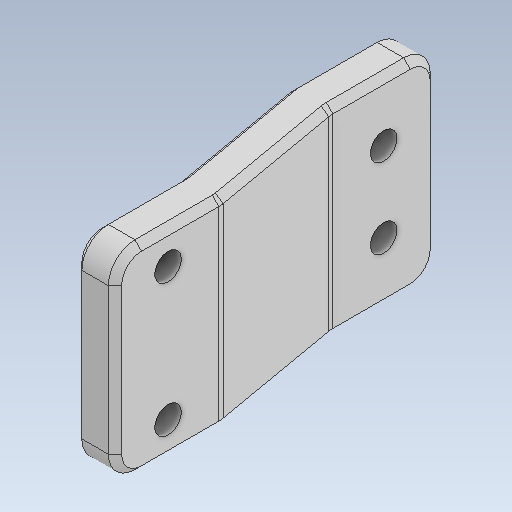
# Autodesk Inventor part: rali-x support_V2
Saved by Autodesk Inventor 2026.2 (Build 302298010, 298A)
## iProperties
Created: 2026-04-29
Part Number: rali-x support_V2
Material: 일반
Document SubType Name: Modeling
Designer: khw
Density: 1 g/cm^3
Appearance: 기본값
Author: khw
Autodesk Inventor part; units mm, degrees
ref_plane "YZ Plane" through (0, 0, 0) normal (1, 0, 0) x (0, 1, 0)
ref_plane "XZ Plane" through (0, 0, 0) normal (0, 1, 0) x (-1, 0, 0)
ref_plane "XY Plane" through (0, 0, 0) normal (0, 0, 1) x (1, 0, 0)
sketch "스케치1" plane through (0, 0, 0) normal (0, 1, 0) x (-1, 0, 0)
  line L0 (0, 0) -> (0, -16)
  line L1 (0, -16) -> (3.5, -36)
  line L2 (3.5, -52) -> (9.5, -52)
  line L3 (9.5, -52) -> (9.5, -36)
  line L4 (9.5, -36) -> (6, -16)
  line L5 (6, -16) -> (6, 0)
  line L6 (6, 0) -> (0, 0)
  line L7 (0, -16) -> (6, -16) construction
  line L8 (3.5, -36) -> (9.5, -36) construction
  line L9 (3.5, -36) -> (3.5, -52)
  point P0 (0, -8)
  point P1 (9.5, -44)
  dimension "d0" = 6
  dimension "d2" = 20
  dimension "d3" = 6
  dimension "d4" = 3.5
  dimension "d5" = 16
  dimension "d6" = 16
  constraints: 20 end point, 4 parallel, 2 midpoint, 2 perpendicular, 1 vertical
  measures "d0" distance from line of L5 point (0, -8)
  measures "d2" vertical distance of L0.end L1.end
  measures "d3" distance from line of point (9.5, -44) L9
  measures "d4" horizontal distance of L1.end L0.end
  measures "d5" distance between parallel lines of L7 L6
  measures "d6" distance of L2.end L3.end
extrude "돌출1" add sketch "스케치1" along normal blind 30
sketch "스케치2" plane through (-6, 0, -16) normal (-1, 0, 0) x (0, 0, 1)
  line L0 (0, 0) -> (16, 0) projected
  line L1 (16, 0) -> (16, 30) construction
  line L2 (0, 30) -> (16, 30) projected
  line L3 (0, 0) -> (0, 30) construction
  line L4 (-36, 0) -> (-20, 0) projected
  line L5 (-20, 0) -> (-20, 30) construction
  line L6 (-36, 30) -> (-20, 30) projected
  line L7 (-36, 0) -> (-36, 30) construction
  line L8 (-28, 0) -> (-28, 30) construction
  line L9 (8, 0) -> (8, 30) construction
  line L10 (16, 15) -> (-36, 15) construction
  circle A0 centre (8, 5) radius 2
  circle A1 centre (-28, 9) radius 2
  circle A2 centre (8, 25) radius 2
  circle A3 centre (-28, 21) radius 2
  line L11 (0, 0) -> (-20, 0) projected
  line L12 (-20, 0) -> (-20, 30) projected
  line L13 (0, 30) -> (-20, 30) projected
  line L14 (0, 0) -> (0, 30) projected
  line L15 (-17, 3) -> (-3, 3)
  line L16 (-3, 3) -> (-3, 27)
  line L17 (-3, 27) -> (-17, 27)
  line L18 (-17, 27) -> (-17, 3)
  line L19 (-3, 23.0307) -> (-14.6846, 3)
  line L20 (-17, 6.9693) -> (-5.3154, 27)
  line L21 (-14.6846, 27) -> (-3, 6.9693)
  line L22 (-5.3154, 3) -> (-17, 23.0307)
  line L23 (-17, 17) -> (-3, 17)
  line L24 (-3, 13) -> (-7.0476, 13)
  line L25 (-7.0476, 13) -> (-17, 13)
  line L26 (-3, 27) -> (-17, 3) construction
  line L27 (-3, 3) -> (-17, 27) construction
  point P0 (16, 0)
  point P1 (-10, 27)
  point P2 (-6.5179, 13)
  point P3 (-10, 11.0307)
  point P4 (-13.4821, 13)
  point P5 (-13.4821, 17)
  point P6 (-10, 18.9693)
  point P7 (-6.5179, 17)
  dimension "d9" = 4
  dimension "d10" = 10
  dimension "d11" = 4
  dimension "d12" = 6
  dimension "d13" = 4
  dimension "d15" = 4
  dimension "d16" = 4
  dimension "d17" = 2
  dimension "d18" = 3
  dimension "d19" = 2
  dimension "d20" = 2
  constraints: 32 end point, 17 point on line, 7 midpoint, 4 centre point, 4 parallel, 2 perpendicular, 2 symmetric about line, 5 other
  measures "d9" diameter of A0
  measures "d10" distance from line of L10 A0.centre
  measures "d11" diameter of A1
  measures "d12" distance from line of L10 A1.centre
  measures "d13" distance between parallel lines of L22 L21
  measures "d15" distance between parallel lines of L24 L23
  measures "d16" distance between parallel lines of L20 L19
  measures "d17" distance between parallel lines of L20 L26
  measures "d18" distance from line of L13 point (-10, 27)
  measures "d19" distance between parallel lines of L22 L27
  measures "d20" distance between parallel lines of L10 L25
extrude "돌출2" cut sketch "스케치2" along normal through all both and the other way through all contours A0 | A1 | A2 | A3
fillet "모깎기1" radius 4 8 edges at (-3, 30, 0) (-3, 0, 0) (-6, 15, -16) (-9.5, 15, -36) (-6.5, 30, -52) (-6.5, 0, -52) (-3.5, 15, -36) (0, 15, -16)
chamfer "모따기1" distance 1 angle 45 32 edges at (-7.75, 30, -26) (-6.015, 30, -15.9987) (-6, 30, -9.8263) (-6, 28.8284, -1.1716) (-6, 15, 0) (-6, 1.1716, -1.1716) (-6, 0, -9.8263) (-6.015, 0, -15.9987) (-7.75, 0, -26) (-9.485, 0, -36.0013) (-9.5, 0, -42.1737) (-9.5, 1.1716, -50.8284) (-9.5, 15, -52) (-9.5, 28.8284, -50.8284) (-9.5, 30, -42.1737) (-9.485, 30, -36.0013) (-1.75, 30, -26) (-3.485, 30, -36.0013) (-3.5, 30, -42.1737) (-3.5, 28.8284, -50.8284) (-3.5, 15, -52) (-3.5, 1.1716, -50.8284) (-3.5, 0, -42.1737) (-3.485, 0, -36.0013) (-1.75, 0, -26) (-0.015, 0, -15.9987) (0, 0, -9.8263) (0, 1.1716, -1.1716) (0, 15, 0) (0, 28.8284, -1.1716) (0, 30, -9.8263) (-0.015, 30, -15.9987)
